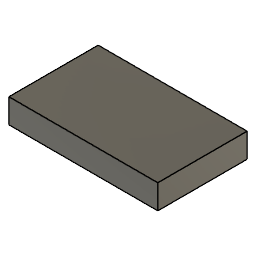
6 pack (Autodesk Fusion 360 design; units mm, degrees)
Autodesk Fusion 360 part; units mm, degrees
sketch "Sketch1" plane through (0, 0, 0) normal (0, 0, 1) x (1, 0, 0)
  line L0 (0, 0) -> (97.79, 0)
  line L1 (97.79, 0) -> (97.79, 58.674)
  line L2 (97.79, 58.674) -> (0, 58.674)
  line L3 (0, 58.674) -> (0, 0)
  dimension "d1" = 58.674
  dimension "d2" = 97.79
  constraint horizontal L0
  constraint vertical L1
  constraint horizontal L2
  constraint vertical L3
  constraint coincident L0.start L3.end
  measures "d1" distance of L0.start L2.end
  measures "d2" distance of L0.start L0.end
extrude "Extrude1" add sketch "Sketch1" along normal blind 16.002
